Autodesk Fusion 360 part; units mm, degrees
(part 19 of 28)
  line L2184 (121.5447, 55.0726) -> (121.7003, 54.9596)
  line L2185 (121.7003, 54.9596) -> (121.8362, 54.8237)
  line L2186 (121.8362, 54.8237) -> (121.9492, 54.6682)
  line L2187 (121.9492, 54.6682) -> (122.0364, 54.4969)
  line L2188 (122.0364, 54.4969) -> (122.0958, 54.3141)
  line L2189 (122.0958, 54.3141) -> (122.1259, 54.1242)
  line L2190 (122.1259, 54.1242) -> (122.1297, 54.0281)
  line L2191 (122.1297, 54.0281) -> (122.1297, 53.4781)
  line L2192 (122.1297, 53.4781) -> (122.1259, 53.382)
  line L2193 (122.1259, 53.382) -> (122.0958, 53.1921)
  line L2194 (122.0958, 53.1921) -> (122.0364, 53.0093)
  line L2195 (122.0364, 53.0093) -> (121.9492, 52.8381)
  line L2196 (121.9492, 52.8381) -> (121.8362, 52.6825)
  line L2197 (121.8362, 52.6825) -> (121.7003, 52.5466)
  line L2198 (121.7003, 52.5466) -> (121.5447, 52.4336)
  line L2199 (121.5447, 52.4336) -> (121.3735, 52.3464)
  line L2200 (121.3735, 52.3464) -> (121.1907, 52.287)
  line L2201 (121.1907, 52.287) -> (121.0008, 52.2569)
  line L2202 (121.0008, 52.2569) -> (120.8086, 52.2569)
  line L2203 (120.8086, 52.2569) -> (120.6187, 52.287)
  line L2204 (120.6187, 52.287) -> (120.4359, 52.3464)
  line L2205 (120.4359, 52.3464) -> (120.2646, 52.4336)
  line L2206 (120.2646, 52.4336) -> (120.1091, 52.5466)
  line L2207 (120.1091, 52.5466) -> (119.9732, 52.6825)
  line L2208 (119.9732, 52.6825) -> (119.8602, 52.8381)
  line L2209 (119.8602, 52.8381) -> (119.7729, 53.0093)
  line L2210 (119.7729, 53.0093) -> (119.7135, 53.1921)
  line L2211 (119.7135, 53.1921) -> (119.6835, 53.382)
  line L2212 (119.6835, 53.382) -> (119.6797, 53.4781)
  line L2213 (119.6797, 53.4781) -> (119.6797, 54.0281)
  line L2214 (119.6797, 54.0281) -> (119.6835, 54.1242)
  line L2215 (119.6835, 54.1242) -> (119.7135, 54.3141)
  line L2216 (119.7135, 54.3141) -> (119.7729, 54.4969)
  line L2217 (119.7729, 54.4969) -> (119.8602, 54.6682)
  line L2218 (119.8602, 54.6682) -> (119.9732, 54.8237)
  line L2219 (119.9732, 54.8237) -> (120.1091, 54.9596)
  line L2220 (120.1091, 54.9596) -> (120.2646, 55.0726)
  line L2221 (120.2646, 55.0726) -> (120.4359, 55.1599)
  line L2222 (120.4359, 55.1599) -> (120.6187, 55.2193)
  line L2223 (120.6187, 55.2193) -> (120.8086, 55.2493)
  line L2224 (120.8086, 55.2493) -> (121.0008, 55.2493)
  line L2225 (121.0008, 55.2493) -> (121.1907, 55.2193)
  line L2226 (33.0099, 62.5572) -> (33.1964, 62.4966)
  line L2227 (33.1964, 62.4966) -> (33.3712, 62.4075)
  line L2228 (33.3712, 62.4075) -> (33.5299, 62.2922)
  line L2229 (33.5299, 62.2922) -> (33.6686, 62.1536)
  line L2230 (33.6686, 62.1536) -> (33.7838, 61.9949)
  line L2231 (33.7838, 61.9949) -> (33.8729, 61.8201)
  line L2232 (33.8729, 61.8201) -> (33.9335, 61.6335)
  line L2233 (33.9335, 61.6335) -> (33.9642, 61.4398)
  line L2234 (33.9642, 61.4398) -> (33.968, 61.3417)
  line L2235 (33.968, 61.3417) -> (33.968, 60.8417)
  line L2236 (33.968, 60.8417) -> (33.9642, 60.7437)
  line L2237 (33.9642, 60.7437) -> (33.9335, 60.5499)
  line L2238 (33.9335, 60.5499) -> (33.8729, 60.3634)
  line L2239 (33.8729, 60.3634) -> (33.7838, 60.1886)
  line L2240 (33.7838, 60.1886) -> (33.6686, 60.0299)
  line L2241 (33.6686, 60.0299) -> (33.5299, 59.8912)
  line L2242 (33.5299, 59.8912) -> (33.3712, 59.7759)
  line L2243 (33.3712, 59.7759) -> (33.1964, 59.6869)
  line L2244 (33.1964, 59.6869) -> (33.0098, 59.6263)
  line L2245 (33.0098, 59.6263) -> (32.8161, 59.5956)
  line L2246 (32.8161, 59.5956) -> (32.62, 59.5956)
  line L2247 (32.62, 59.5956) -> (32.4262, 59.6263)
  line L2248 (32.4262, 59.6263) -> (32.2397, 59.6869)
  line L2249 (32.2397, 59.6869) -> (32.0649, 59.7759)
  line L2250 (32.0649, 59.7759) -> (31.9062, 59.8912)
  line L2251 (31.9062, 59.8912) -> (31.7675, 60.0299)
  line L2252 (31.7675, 60.0299) -> (31.6522, 60.1886)
  line L2253 (31.6522, 60.1886) -> (31.5632, 60.3634)
  line L2254 (31.5632, 60.3634) -> (31.5026, 60.5499)
  line L2255 (31.5026, 60.5499) -> (31.4719, 60.7437)
  line L2256 (31.4719, 60.7437) -> (31.468, 60.8417)
  line L2257 (31.468, 60.8417) -> (31.468, 61.3417)
  line L2258 (31.468, 61.3417) -> (31.4719, 61.4398)
  line L2259 (31.4719, 61.4398) -> (31.5026, 61.6335)
  line L2260 (31.5026, 61.6335) -> (31.5632, 61.8201)
  line L2261 (31.5632, 61.8201) -> (31.6522, 61.9949)
  line L2262 (31.6522, 61.9949) -> (31.7675, 62.1536)
  line L2263 (31.7675, 62.1536) -> (31.9062, 62.2922)
  line L2264 (31.9062, 62.2922) -> (32.0649, 62.4075)
  line L2265 (32.0649, 62.4075) -> (32.2397, 62.4966)
  line L2266 (32.2397, 62.4966) -> (32.4262, 62.5572)
  line L2267 (32.4262, 62.5572) -> (32.62, 62.5879)
  line L2268 (32.62, 62.5879) -> (32.8161, 62.5879)
  line L2269 (32.8161, 62.5879) -> (33.0098, 62.5572)
  line L2270 (67.9348, 62.5572) -> (68.1214, 62.4966)
  line L2271 (68.1214, 62.4966) -> (68.2962, 62.4075)
  line L2272 (68.2962, 62.4075) -> (68.4549, 62.2922)
  line L2273 (68.4549, 62.2922) -> (68.5935, 62.1536)
  line L2274 (68.5935, 62.1536) -> (68.7088, 61.9949)
  line L2275 (68.7088, 61.9949) -> (68.7979, 61.8201)
  line L2276 (68.7979, 61.8201) -> (68.8585, 61.6335)
  line L2277 (68.8585, 61.6335) -> (68.8892, 61.4398)
  line L2278 (68.8892, 61.4398) -> (68.893, 61.3417)
  line L2279 (68.893, 61.3417) -> (68.893, 60.8417)
  line L2280 (68.893, 60.8417) -> (68.8892, 60.7437)
  line L2281 (68.8892, 60.7437) -> (68.8585, 60.5499)
  line L2282 (68.8585, 60.5499) -> (68.7979, 60.3634)
  line L2283 (68.7979, 60.3634) -> (68.7088, 60.1886)
  line L2284 (68.7088, 60.1886) -> (68.5935, 60.0299)
  line L2285 (68.5935, 60.0299) -> (68.4549, 59.8912)
  line L2286 (68.4549, 59.8912) -> (68.2962, 59.7759)
  line L2287 (68.2962, 59.7759) -> (68.1214, 59.6869)
  line L2288 (68.1214, 59.6869) -> (67.9348, 59.6263)
  line L2289 (67.9348, 59.6263) -> (67.7411, 59.5956)
  line L2290 (67.7411, 59.5956) -> (67.545, 59.5956)
  line L2291 (67.545, 59.5956) -> (67.3512, 59.6263)
  line L2292 (67.3512, 59.6263) -> (67.1647, 59.6869)
  line L2293 (67.1647, 59.6869) -> (66.9899, 59.7759)
  line L2294 (66.9899, 59.7759) -> (66.8312, 59.8912)
  line L2295 (66.8312, 59.8912) -> (66.6925, 60.0299)
  line L2296 (66.6925, 60.0299) -> (66.5772, 60.1886)
  line L2297 (66.5772, 60.1886) -> (66.4882, 60.3634)
  line L2298 (66.4882, 60.3634) -> (66.4276, 60.5499)
  line L2299 (66.4276, 60.5499) -> (66.3969, 60.7437)
  line L2300 (66.3969, 60.7437) -> (66.393, 60.8417)
  line L2301 (66.393, 60.8417) -> (66.393, 61.3417)
  line L2302 (66.393, 61.3417) -> (66.3969, 61.4398)
  line L2303 (66.3969, 61.4398) -> (66.4276, 61.6335)
  line L2304 (66.4276, 61.6335) -> (66.4882, 61.8201)
  line L2305 (66.4882, 61.8201) -> (66.5772, 61.9949)
  line L2306 (66.5772, 61.9949) -> (66.6925, 62.1536)
  line L2307 (66.6925, 62.1536) -> (66.8312, 62.2922)
  line L2308 (66.8312, 62.2922) -> (66.9899, 62.4075)
  line L2309 (66.9899, 62.4075) -> (67.1647, 62.4966)
  line L2310 (67.1647, 62.4966) -> (67.3512, 62.5572)
  line L2311 (67.3512, 62.5572) -> (67.545, 62.5879)
  line L2312 (67.545, 62.5879) -> (67.7411, 62.5879)
  line L2313 (67.7411, 62.5879) -> (67.9348, 62.5572)
  line L2314 (102.8598, 62.5572) -> (103.0464, 62.4966)
  line L2315 (103.0464, 62.4966) -> (103.2212, 62.4075)
  line L2316 (103.2212, 62.4075) -> (103.3799, 62.2922)
  line L2317 (103.3799, 62.2922) -> (103.5186, 62.1536)
  line L2318 (103.5186, 62.1536) -> (103.6338, 61.9949)
  line L2319 (103.6338, 61.9949) -> (103.7229, 61.8201)
  line L2320 (103.7229, 61.8201) -> (103.7835, 61.6335)
  line L2321 (103.7835, 61.6335) -> (103.8142, 61.4398)
  line L2322 (103.8142, 61.4398) -> (103.818, 61.3417)
  line L2323 (103.818, 61.3417) -> (103.818, 60.8417)
  line L2324 (103.818, 60.8417) -> (103.8142, 60.7437)
  line L2325 (103.8142, 60.7437) -> (103.7835, 60.5499)
  line L2326 (103.7835, 60.5499) -> (103.7229, 60.3634)
  line L2327 (103.7229, 60.3634) -> (103.6338, 60.1886)
  line L2328 (103.6338, 60.1886) -> (103.5186, 60.0299)
  line L2329 (103.5186, 60.0299) -> (103.3799, 59.8912)
  line L2330 (103.3799, 59.8912) -> (103.2212, 59.7759)
  line L2331 (103.2212, 59.7759) -> (103.0464, 59.6869)
  line L2332 (103.0464, 59.6869) -> (102.8598, 59.6263)
  line L2333 (102.8598, 59.6263) -> (102.6661, 59.5956)
  line L2334 (102.6661, 59.5956) -> (102.47, 59.5956)
  line L2335 (102.47, 59.5956) -> (102.2762, 59.6263)
  line L2336 (102.2762, 59.6263) -> (102.0897, 59.6869)
  line L2337 (102.0897, 59.6869) -> (101.9149, 59.7759)
  line L2338 (101.9149, 59.7759) -> (101.7562, 59.8912)
  line L2339 (101.7562, 59.8912) -> (101.6175, 60.0299)
  line L2340 (101.6175, 60.0299) -> (101.5022, 60.1886)
  line L2341 (101.5022, 60.1886) -> (101.4132, 60.3634)
  line L2342 (101.4132, 60.3634) -> (101.3526, 60.5499)
  line L2343 (101.3526, 60.5499) -> (101.3219, 60.7437)
  line L2344 (101.3219, 60.7437) -> (101.318, 60.8417)
  line L2345 (101.318, 60.8417) -> (101.318, 61.3417)
  line L2346 (101.318, 61.3417) -> (101.3219, 61.4398)
  line L2347 (101.3219, 61.4398) -> (101.3526, 61.6335)
  line L2348 (101.3526, 61.6335) -> (101.4132, 61.8201)
  line L2349 (101.4132, 61.8201) -> (101.5022, 61.9949)
  line L2350 (101.5022, 61.9949) -> (101.6175, 62.1536)
  line L2351 (101.6175, 62.1536) -> (101.7562, 62.2922)
  line L2352 (101.7562, 62.2922) -> (101.9149, 62.4075)
  line L2353 (101.9149, 62.4075) -> (102.0897, 62.4966)
  line L2354 (102.0897, 62.4966) -> (102.2762, 62.5572)
  line L2355 (102.2762, 62.5572) -> (102.47, 62.5879)
  line L2356 (102.47, 62.5879) -> (102.6661, 62.5879)
  line L2357 (102.6661, 62.5879) -> (102.8598, 62.5572)
  line L2358 (137.7849, 62.5572) -> (137.9714, 62.4966)
  line L2359 (137.9714, 62.4966) -> (138.1462, 62.4075)
  line L2360 (138.1462, 62.4075) -> (138.3049, 62.2922)
  line L2361 (138.3049, 62.2922) -> (138.4436, 62.1536)
  line L2362 (138.4436, 62.1536) -> (138.5588, 61.9949)
  line L2363 (138.5588, 61.9949) -> (138.6479, 61.8201)
  line L2364 (138.6479, 61.8201) -> (138.7085, 61.6335)
  line L2365 (138.7085, 61.6335) -> (138.7392, 61.4398)
  line L2366 (138.7392, 61.4398) -> (138.743, 61.3417)
  line L2367 (138.743, 61.3417) -> (138.743, 60.8417)
  line L2368 (138.743, 60.8417) -> (138.7392, 60.7437)
  line L2369 (138.7392, 60.7437) -> (138.7085, 60.5499)
  line L2370 (138.7085, 60.5499) -> (138.6479, 60.3634)
  line L2371 (138.6479, 60.3634) -> (138.5588, 60.1886)
  line L2372 (138.5588, 60.1886) -> (138.4436, 60.0299)
  line L2373 (138.4436, 60.0299) -> (138.3049, 59.8912)
  line L2374 (138.3049, 59.8912) -> (138.1462, 59.7759)
  line L2375 (138.1462, 59.7759) -> (137.9714, 59.6869)
  line L2376 (137.9714, 59.6869) -> (137.7849, 59.6263)
  line L2377 (137.7849, 59.6263) -> (137.5911, 59.5956)
  line L2378 (137.5911, 59.5956) -> (137.395, 59.5956)
  line L2379 (137.395, 59.5956) -> (137.2012, 59.6263)
  line L2380 (137.2012, 59.6263) -> (137.0147, 59.6869)
  line L2381 (137.0147, 59.6869) -> (136.8399, 59.7759)
  line L2382 (136.8399, 59.7759) -> (136.6812, 59.8912)
  line L2383 (136.6812, 59.8912) -> (136.5425, 60.0299)
  line L2384 (136.5425, 60.0299) -> (136.4272, 60.1886)
  line L2385 (136.4272, 60.1886) -> (136.3382, 60.3634)
  line L2386 (136.3382, 60.3634) -> (136.2776, 60.5499)
  line L2387 (136.2776, 60.5499) -> (136.2469, 60.7437)
  line L2388 (136.2469, 60.7437) -> (136.243, 60.8417)
  line L2389 (136.243, 60.8417) -> (136.243, 61.3417)
  line L2390 (136.243, 61.3417) -> (136.2469, 61.4398)
  line L2391 (136.2469, 61.4398) -> (136.2776, 61.6335)
  line L2392 (136.2776, 61.6335) -> (136.3382, 61.8201)
  line L2393 (136.3382, 61.8201) -> (136.4272, 61.9949)
  line L2394 (136.4272, 61.9949) -> (136.5425, 62.1536)
  line L2395 (136.5425, 62.1536) -> (136.6812, 62.2922)
  line L2396 (136.6812, 62.2922) -> (136.8399, 62.4075)
  line L2397 (136.8399, 62.4075) -> (137.0147, 62.4966)
  line L2398 (137.0147, 62.4966) -> (137.2012, 62.5572)
  line L2399 (137.2012, 62.5572) -> (137.395, 62.5879)
  line L2400 (137.395, 62.5879) -> (137.5911, 62.5879)
  line L2401 (137.5911, 62.5879) -> (137.7849, 62.5572)
  line L2402 (16.536, 65.4179) -> (16.7297, 65.3872)
  line L2403 (16.7297, 65.3872) -> (16.9162, 65.3266)
  line L2404 (16.9162, 65.3266) -> (17.091, 65.2376)
  line L2405 (17.091, 65.2376) -> (17.2497, 65.1223)
  line L2406 (17.2497, 65.1223) -> (17.3884, 64.9836)
  line L2407 (17.3884, 64.9836) -> (17.5037, 64.8249)
  line L2408 (17.5037, 64.8249) -> (17.5927, 64.6501)
  line L2409 (17.5927, 64.6501) -> (17.6534, 64.4636)
  line L2410 (17.6534, 64.4636) -> (17.684, 64.2698)
  line L2411 (17.684, 64.2698) -> (17.684, 64.0737)
  line L2412 (17.684, 64.0737) -> (17.6534, 63.88)
  line L2413 (17.6534, 63.88) -> (17.5927, 63.6934)
  line L2414 (17.5927, 63.6934) -> (17.5037, 63.5186)
  line L2415 (17.5037, 63.5186) -> (17.3884, 63.36)
  line L2416 (17.3884, 63.36) -> (17.2497, 63.2213)
  line L2417 (17.2497, 63.2213) -> (17.091, 63.106)
  line L2418 (17.091, 63.106) -> (16.9162, 63.0169)
  line L2419 (16.9162, 63.0169) -> (16.7297, 62.9563)
  line L2420 (16.7297, 62.9563) -> (16.536, 62.9256)
  line L2421 (16.536, 62.9256) -> (16.4379, 62.9218)
  line L2422 (16.4379, 62.9218) -> (15.9379, 62.9218)
  line L2423 (15.9379, 62.9218) -> (15.8398, 62.9256)
  line L2424 (15.8398, 62.9256) -> (15.6461, 62.9563)
  line L2425 (15.6461, 62.9563) -> (15.4595, 63.0169)
  line L2426 (15.4595, 63.0169) -> (15.2848, 63.106)
  line L2427 (15.2848, 63.106) -> (15.1261, 63.2213)
  line L2428 (15.1261, 63.2213) -> (14.9874, 63.36)
  line L2429 (14.9874, 63.36) -> (14.8721, 63.5186)
  line L2430 (14.8721, 63.5186) -> (14.783, 63.6934)
  line L2431 (14.783, 63.6934) -> (14.7224, 63.88)
  line L2432 (14.7224, 63.88) -> (14.6917, 64.0737)
  line L2433 (14.6917, 64.0737) -> (14.6917, 64.2698)
  line L2434 (14.6917, 64.2698) -> (14.7224, 64.4636)
  line L2435 (14.7224, 64.4636) -> (14.783, 64.6501)
  line L2436 (14.783, 64.6501) -> (14.8721, 64.8249)
  line L2437 (14.8721, 64.8249) -> (14.9874, 64.9836)
  line L2438 (14.9874, 64.9836) -> (15.1261, 65.1223)
  line L2439 (15.1261, 65.1223) -> (15.2848, 65.2376)
  line L2440 (15.2848, 65.2376) -> (15.4595, 65.3266)
  line L2441 (15.4595, 65.3266) -> (15.6461, 65.3872)
  line L2442 (15.6461, 65.3872) -> (15.8398, 65.4179)
  line L2443 (15.8398, 65.4179) -> (15.9379, 65.4218)
  line L2444 (15.9379, 65.4218) -> (16.4379, 65.4218)
  line L2445 (16.4379, 65.4218) -> (16.536, 65.4179)
  line L2446 (24.156, 65.4179) -> (24.3497, 65.3872)
  line L2447 (24.3497, 65.3872) -> (24.5362, 65.3266)
  line L2448 (24.5362, 65.3266) -> (24.711, 65.2376)
  line L2449 (24.711, 65.2376) -> (24.8697, 65.1223)
  line L2450 (24.8697, 65.1223) -> (25.0084, 64.9836)
  line L2451 (25.0084, 64.9836) -> (25.1237, 64.8249)
  line L2452 (25.1237, 64.8249) -> (25.2127, 64.6501)
  line L2453 (25.2127, 64.6501) -> (25.2734, 64.4636)
  line L2454 (25.2734, 64.4636) -> (25.304, 64.2698)
  line L2455 (25.304, 64.2698) -> (25.304, 64.0737)
  line L2456 (25.304, 64.0737) -> (25.2734, 63.88)
  line L2457 (25.2734, 63.88) -> (25.2127, 63.6934)
  line L2458 (25.2127, 63.6934) -> (25.1237, 63.5186)
  line L2459 (25.1237, 63.5186) -> (25.0084, 63.36)
  line L2460 (25.0084, 63.36) -> (24.8697, 63.2213)
  line L2461 (24.8697, 63.2213) -> (24.711, 63.106)
  line L2462 (24.711, 63.106) -> (24.5362, 63.0169)
  line L2463 (24.5362, 63.0169) -> (24.3497, 62.9563)
  line L2464 (24.3497, 62.9563) -> (24.156, 62.9256)
  line L2465 (24.156, 62.9256) -> (24.0579, 62.9218)
  line L2466 (24.0579, 62.9218) -> (23.5579, 62.9218)
  line L2467 (23.5579, 62.9218) -> (23.4598, 62.9256)
  line L2468 (23.4598, 62.9256) -> (23.2661, 62.9563)
  line L2469 (23.2661, 62.9563) -> (23.0795, 63.0169)
  line L2470 (23.0795, 63.0169) -> (22.9048, 63.106)
  line L2471 (22.9048, 63.106) -> (22.7461, 63.2213)
  line L2472 (22.7461, 63.2213) -> (22.6074, 63.36)
  line L2473 (22.6074, 63.36) -> (22.4921, 63.5186)
  line L2474 (22.4921, 63.5186) -> (22.403, 63.6934)
  line L2475 (22.403, 63.6934) -> (22.3424, 63.88)
  line L2476 (22.3424, 63.88) -> (22.3117, 64.0737)
  line L2477 (22.3117, 64.0737) -> (22.3117, 64.2698)
  line L2478 (22.3117, 64.2698) -> (22.3424, 64.4636)
  line L2479 (22.3424, 64.4636) -> (22.403, 64.6501)
  line L2480 (22.403, 64.6501) -> (22.4921, 64.8249)
  line L2481 (22.4921, 64.8249) -> (22.6074, 64.9836)
  line L2482 (22.6074, 64.9836) -> (22.7461, 65.1223)
  line L2483 (22.7461, 65.1223) -> (22.9048, 65.2376)
  line L2484 (22.9048, 65.2376) -> (23.0795, 65.3266)
  line L2485 (23.0795, 65.3266) -> (23.2661, 65.3872)
  line L2486 (23.2661, 65.3872) -> (23.4598, 65.4179)
  line L2487 (23.4598, 65.4179) -> (23.5579, 65.4218)
  line L2488 (23.5579, 65.4218) -> (24.0579, 65.4218)
  line L2489 (24.0579, 65.4218) -> (24.156, 65.4179)
  line L2490 (51.461, 65.4179) -> (51.6547, 65.3872)
  line L2491 (51.6547, 65.3872) -> (51.8412, 65.3266)
  line L2492 (51.8412, 65.3266) -> (52.016, 65.2376)
  line L2493 (52.016, 65.2376) -> (52.1747, 65.1223)
  line L2494 (52.1747, 65.1223) -> (52.3134, 64.9836)
  line L2495 (52.3134, 64.9836) -> (52.4287, 64.8249)
  line L2496 (52.4287, 64.8249) -> (52.5177, 64.6501)
  line L2497 (52.5177, 64.6501) -> (52.5784, 64.4636)
  line L2498 (52.5784, 64.4636) -> (52.609, 64.2698)
  line L2499 (52.609, 64.2698) -> (52.609, 64.0737)
  line L2500 (52.609, 64.0737) -> (52.5783, 63.88)
  line L2501 (52.5783, 63.88) -> (52.5177, 63.6934)
  line L2502 (52.5177, 63.6934) -> (52.4287, 63.5186)
  line L2503 (52.4287, 63.5186) -> (52.3134, 63.36)
  line L2504 (52.3134, 63.36) -> (52.1747, 63.2213)
  line L2505 (52.1747, 63.2213) -> (52.016, 63.106)
  line L2506 (52.016, 63.106) -> (51.8412, 63.0169)
  line L2507 (51.8412, 63.0169) -> (51.6547, 62.9563)
  line L2508 (51.6547, 62.9563) -> (51.461, 62.9256)
  line L2509 (51.461, 62.9256) -> (51.3629, 62.9218)
  line L2510 (51.3629, 62.9218) -> (50.8629, 62.9218)
  line L2511 (50.8629, 62.9218) -> (50.7648, 62.9256)
  line L2512 (50.7648, 62.9256) -> (50.5711, 62.9563)
  line L2513 (50.5711, 62.9563) -> (50.3845, 63.0169)
  line L2514 (50.3845, 63.0169) -> (50.2098, 63.106)
  line L2515 (50.2098, 63.106) -> (50.0511, 63.2213)
  line L2516 (50.0511, 63.2213) -> (49.9124, 63.36)
  line L2517 (49.9124, 63.36) -> (49.7971, 63.5186)
  line L2518 (49.7971, 63.5186) -> (49.708, 63.6934)
  line L2519 (49.708, 63.6934) -> (49.6474, 63.88)
  line L2520 (49.6474, 63.88) -> (49.6167, 64.0737)
  line L2521 (49.6167, 64.0737) -> (49.6167, 64.2698)
  line L2522 (49.6167, 64.2698) -> (49.6474, 64.4636)
  line L2523 (49.6474, 64.4636) -> (49.708, 64.6501)
  line L2524 (49.708, 64.6501) -> (49.7971, 64.8249)
  line L2525 (49.7971, 64.8249) -> (49.9124, 64.9836)
  line L2526 (49.9124, 64.9836) -> (50.0511, 65.1223)
  line L2527 (50.0511, 65.1223) -> (50.2098, 65.2376)
  line L2528 (50.2098, 65.2376) -> (50.3845, 65.3266)
  line L2529 (50.3845, 65.3266) -> (50.5711, 65.3872)
  line L2530 (50.5711, 65.3872) -> (50.7648, 65.4179)
  line L2531 (50.7648, 65.4179) -> (50.8629, 65.4218)
  line L2532 (50.8629, 65.4218) -> (51.3629, 65.4218)
  line L2533 (51.3629, 65.4218) -> (51.461, 65.4179)
  line L2534 (59.081, 65.4179) -> (59.2747, 65.3872)
  line L2535 (59.2747, 65.3872) -> (59.4612, 65.3266)
  line L2536 (59.4612, 65.3266) -> (59.636, 65.2376)
  line L2537 (59.636, 65.2376) -> (59.7947, 65.1223)
  line L2538 (59.7947, 65.1223) -> (59.9334, 64.9836)
  line L2539 (59.9334, 64.9836) -> (60.0487, 64.8249)
  line L2540 (60.0487, 64.8249) -> (60.1377, 64.6501)
  line L2541 (60.1377, 64.6501) -> (60.1984, 64.4636)
  line L2542 (60.1984, 64.4636) -> (60.229, 64.2698)
  line L2543 (60.229, 64.2698) -> (60.229, 64.0737)
  line L2544 (60.229, 64.0737) -> (60.1983, 63.88)
  line L2545 (60.1983, 63.88) -> (60.1377, 63.6934)
  line L2546 (60.1377, 63.6934) -> (60.0487, 63.5186)
  line L2547 (60.0487, 63.5186) -> (59.9334, 63.36)
  line L2548 (59.9334, 63.36) -> (59.7947, 63.2213)
  line L2549 (59.7947, 63.2213) -> (59.636, 63.106)
  line L2550 (59.636, 63.106) -> (59.4612, 63.0169)
  line L2551 (59.4612, 63.0169) -> (59.2747, 62.9563)
  line L2552 (59.2747, 62.9563) -> (59.081, 62.9256)
  line L2553 (59.081, 62.9256) -> (58.9829, 62.9218)
  line L2554 (58.9829, 62.9218) -> (58.4829, 62.9218)
  line L2555 (58.4829, 62.9218) -> (58.3848, 62.9256)
  line L2556 (58.3848, 62.9256) -> (58.1911, 62.9563)
  line L2557 (58.1911, 62.9563) -> (58.0045, 63.0169)
  line L2558 (58.0045, 63.0169) -> (57.8298, 63.106)
  line L2559 (57.8298, 63.106) -> (57.6711, 63.2213)
  line L2560 (57.6711, 63.2213) -> (57.5324, 63.36)
  line L2561 (57.5324, 63.36) -> (57.4171, 63.5186)
  line L2562 (57.4171, 63.5186) -> (57.328, 63.6934)
  line L2563 (57.328, 63.6934) -> (57.2674, 63.88)
  line L2564 (57.2674, 63.88) -> (57.2367, 64.0737)
  line L2565 (57.2367, 64.0737) -> (57.2367, 64.2698)
  line L2566 (57.2367, 64.2698) -> (57.2674, 64.4636)
  line L2567 (57.2674, 64.4636) -> (57.328, 64.6501)
  line L2568 (57.328, 64.6501) -> (57.4171, 64.8249)
  line L2569 (57.4171, 64.8249) -> (57.5324, 64.9836)
  line L2570 (57.5324, 64.9836) -> (57.6711, 65.1223)
  line L2571 (57.6711, 65.1223) -> (57.8298, 65.2376)
  line L2572 (57.8298, 65.2376) -> (58.0045, 65.3266)
  line L2573 (58.0045, 65.3266) -> (58.1911, 65.3872)
  line L2574 (58.1911, 65.3872) -> (58.3848, 65.4179)
  line L2575 (58.3848, 65.4179) -> (58.4829, 65.4218)
  line L2576 (58.4829, 65.4218) -> (58.9829, 65.4218)
  line L2577 (58.9829, 65.4218) -> (59.081, 65.4179)
  line L2578 (86.386, 65.4179) -> (86.5797, 65.3872)
  line L2579 (86.5797, 65.3872) -> (86.7662, 65.3266)
  line L2580 (86.7662, 65.3266) -> (86.941, 65.2376)
  line L2581 (86.941, 65.2376) -> (87.0997, 65.1223)
  line L2582 (87.0997, 65.1223) -> (87.2384, 64.9836)
  line L2583 (87.2384, 64.9836) -> (87.3537, 64.8249)
  line L2584 (87.3537, 64.8249) -> (87.4427, 64.6501)
  line L2585 (87.4427, 64.6501) -> (87.5034, 64.4636)
  line L2586 (87.5034, 64.4636) -> (87.534, 64.2698)
  line L2587 (87.534, 64.2698) -> (87.534, 64.0737)
  line L2588 (87.534, 64.0737) -> (87.5034, 63.88)
  line L2589 (87.5033, 63.88) -> (87.4427, 63.6934)
  line L2590 (87.4427, 63.6934) -> (87.3537, 63.5186)
  line L2591 (87.3537, 63.5186) -> (87.2384, 63.36)
  line L2592 (87.2384, 63.36) -> (87.0997, 63.2213)
  line L2593 (87.0997, 63.2213) -> (86.941, 63.106)
  line L2594 (86.941, 63.106) -> (86.7662, 63.0169)
  line L2595 (86.7662, 63.0169) -> (86.5797, 62.9563)
  line L2596 (86.5797, 62.9563) -> (86.386, 62.9256)
  line L2597 (86.386, 62.9256) -> (86.2879, 62.9218)
  line L2598 (86.2879, 62.9218) -> (85.7879, 62.9218)
  line L2599 (85.7879, 62.9218) -> (85.6898, 62.9256)
  line L2600 (85.6898, 62.9256) -> (85.4961, 62.9563)
  line L2601 (85.4961, 62.9563) -> (85.3095, 63.0169)
  line L2602 (85.3095, 63.0169) -> (85.1348, 63.106)
  line L2603 (85.1348, 63.106) -> (84.9761, 63.2213)
  line L2604 (84.9761, 63.2213) -> (84.8374, 63.36)
  line L2605 (84.8374, 63.36) -> (84.7221, 63.5186)
  line L2606 (84.7221, 63.5186) -> (84.633, 63.6934)
  line L2607 (84.633, 63.6934) -> (84.5724, 63.88)
  line L2608 (84.5724, 63.88) -> (84.5417, 64.0737)
  line L2609 (84.5417, 64.0737) -> (84.5417, 64.2698)
  line L2610 (84.5417, 64.2698) -> (84.5724, 64.4636)
  line L2611 (84.5724, 64.4636) -> (84.633, 64.6501)
  line L2612 (84.633, 64.6501) -> (84.7221, 64.8249)
  line L2613 (84.7221, 64.8249) -> (84.8374, 64.9836)
  line L2614 (84.8374, 64.9836) -> (84.9761, 65.1223)
  line L2615 (84.9761, 65.1223) -> (85.1348, 65.2376)
  line L2616 (85.1348, 65.2376) -> (85.3095, 65.3266)
  line L2617 (85.3095, 65.3266) -> (85.4961, 65.3872)
  line L2618 (85.4961, 65.3872) -> (85.6898, 65.4179)
  line L2619 (85.6898, 65.4179) -> (85.7879, 65.4218)
  line L2620 (85.7879, 65.4218) -> (86.2879, 65.4218)
  line L2621 (86.2879, 65.4218) -> (86.386, 65.4179)
  line L2622 (94.006, 65.4179) -> (94.1997, 65.3872)
  line L2623 (94.1997, 65.3872) -> (94.3862, 65.3266)
  line L2624 (94.3862, 65.3266) -> (94.561, 65.2376)
  line L2625 (94.561, 65.2376) -> (94.7197, 65.1223)
  line L2626 (94.7197, 65.1223) -> (94.8584, 64.9836)
  line L2627 (94.8584, 64.9836) -> (94.9737, 64.8249)
  line L2628 (94.9737, 64.8249) -> (95.0627, 64.6501)
  line L2629 (95.0627, 64.6501) -> (95.1233, 64.4636)
  line L2630 (95.1233, 64.4636) -> (95.154, 64.2698)
  line L2631 (95.154, 64.2698) -> (95.154, 64.0737)
  line L2632 (95.154, 64.0737) -> (95.1233, 63.88)
  line L2633 (95.1233, 63.88) -> (95.0627, 63.6934)
  line L2634 (95.0627, 63.6934) -> (94.9737, 63.5186)
  line L2635 (94.9737, 63.5186) -> (94.8584, 63.36)
  line L2636 (94.8584, 63.36) -> (94.7197, 63.2213)
  line L2637 (94.7197, 63.2213) -> (94.561, 63.106)
  line L2638 (94.561, 63.106) -> (94.3862, 63.0169)
  line L2639 (94.3862, 63.0169) -> (94.1997, 62.9563)
  line L2640 (94.1997, 62.9563) -> (94.006, 62.9256)
  line L2641 (94.006, 62.9256) -> (93.9079, 62.9218)
  line L2642 (93.9079, 62.9218) -> (93.4079, 62.9218)
  line L2643 (93.4079, 62.9218) -> (93.3098, 62.9256)
  line L2644 (93.3098, 62.9256) -> (93.1161, 62.9563)
  line L2645 (93.1161, 62.9563) -> (92.9295, 63.0169)
  line L2646 (92.9295, 63.0169) -> (92.7548, 63.106)
  line L2647 (92.7548, 63.106) -> (92.5961, 63.2213)
  line L2648 (92.5961, 63.2213) -> (92.4574, 63.36)
  line L2649 (92.4574, 63.36) -> (92.3421, 63.5186)
  line L2650 (92.3421, 63.5186) -> (92.253, 63.6934)
  line L2651 (92.253, 63.6934) -> (92.1924, 63.88)
  line L2652 (92.1924, 63.88) -> (92.1617, 64.0737)
  line L2653 (92.1617, 64.0737) -> (92.1617, 64.2698)
  line L2654 (92.1617, 64.2698) -> (92.1924, 64.4636)
  line L2655 (92.1924, 64.4636) -> (92.253, 64.6501)
  line L2656 (92.253, 64.6501) -> (92.3421, 64.8249)
  line L2657 (92.3421, 64.8249) -> (92.4574, 64.9836)
  line L2658 (92.4574, 64.9836) -> (92.5961, 65.1223)
  line L2659 (92.5961, 65.1223) -> (92.7548, 65.2376)
  line L2660 (92.7548, 65.2376) -> (92.9295, 65.3266)
  line L2661 (92.9295, 65.3266) -> (93.1161, 65.3872)
  line L2662 (93.1161, 65.3872) -> (93.3098, 65.4179)
  line L2663 (93.3098, 65.4179) -> (93.4079, 65.4218)
  line L2664 (93.4079, 65.4218) -> (93.9079, 65.4218)
  line L2665 (93.9079, 65.4218) -> (94.006, 65.4179)
  line L2666 (121.311, 65.4179) -> (121.5047, 65.3872)
  line L2667 (121.5047, 65.3872) -> (121.6912, 65.3266)
  line L2668 (121.6912, 65.3266) -> (121.866, 65.2376)
  line L2669 (121.866, 65.2376) -> (122.0247, 65.1223)
  line L2670 (122.0247, 65.1223) -> (122.1634, 64.9836)
  line L2671 (122.1634, 64.9836) -> (122.2787, 64.8249)
  line L2672 (122.2787, 64.8249) -> (122.3677, 64.6501)
  line L2673 (122.3677, 64.6501) -> (122.4283, 64.4636)
  line L2674 (122.4283, 64.4636) -> (122.459, 64.2698)
  line L2675 (122.459, 64.2698) -> (122.459, 64.0737)
  line L2676 (122.459, 64.0737) -> (122.4283, 63.88)
  line L2677 (122.4283, 63.88) -> (122.3677, 63.6934)
  line L2678 (122.3677, 63.6934) -> (122.2787, 63.5186)
  line L2679 (122.2787, 63.5186) -> (122.1634, 63.36)
  line L2680 (122.1634, 63.36) -> (122.0247, 63.2213)
  line L2681 (122.0247, 63.2213) -> (121.866, 63.106)
  line L2682 (121.866, 63.106) -> (121.6912, 63.0169)
  line L2683 (121.6912, 63.0169) -> (121.5047, 62.9563)
  line L2684 (121.5047, 62.9563) -> (121.311, 62.9256)
  line L2685 (121.311, 62.9256) -> (121.2129, 62.9218)
  line L2686 (121.2129, 62.9218) -> (120.7129, 62.9218)
  line L2687 (120.7129, 62.9218) -> (120.6148, 62.9256)
  line L2688 (120.6148, 62.9256) -> (120.4211, 62.9563)
  line L2689 (120.4211, 62.9563) -> (120.2345, 63.0169)
  line L2690 (120.2345, 63.0169) -> (120.0598, 63.106)
  line L2691 (120.0598, 63.106) -> (119.9011, 63.2213)
  line L2692 (119.9011, 63.2213) -> (119.7624, 63.36)
  line L2693 (119.7624, 63.36) -> (119.6471, 63.5186)
  line L2694 (119.6471, 63.5186) -> (119.558, 63.6934)
  line L2695 (119.558, 63.6934) -> (119.4974, 63.88)
  line L2696 (119.4974, 63.88) -> (119.4667, 64.0737)
  line L2697 (119.4667, 64.0737) -> (119.4667, 64.2698)
  line L2698 (119.4667, 64.2698) -> (119.4974, 64.4636)
  line L2699 (119.4974, 64.4636) -> (119.558, 64.6501)
  line L2700 (119.558, 64.6501) -> (119.6471, 64.8249)
  line L2701 (119.6471, 64.8249) -> (119.7624, 64.9836)
  line L2702 (119.7624, 64.9836) -> (119.9011, 65.1223)
  line L2703 (119.9011, 65.1223) -> (120.0598, 65.2376)
  line L2704 (120.0598, 65.2376) -> (120.2345, 65.3266)
  line L2705 (120.2345, 65.3266) -> (120.4211, 65.3872)
  line L2706 (120.4211, 65.3872) -> (120.6148, 65.4179)
  line L2707 (120.6148, 65.4179) -> (120.7129, 65.4218)
  line L2708 (120.7129, 65.4218) -> (121.2129, 65.4218)
  line L2709 (121.2129, 65.4218) -> (121.311, 65.4179)
  line L2710 (128.931, 65.4179) -> (129.1247, 65.3872)
  line L2711 (129.1247, 65.3872) -> (129.3112, 65.3266)
  line L2712 (129.3112, 65.3266) -> (129.486, 65.2376)
  line L2713 (129.486, 65.2376) -> (129.6447, 65.1223)
  line L2714 (129.6447, 65.1223) -> (129.7834, 64.9836)
  line L2715 (129.7834, 64.9836) -> (129.8987, 64.8249)
  line L2716 (129.8987, 64.8249) -> (129.9877, 64.6501)
  line L2717 (129.9877, 64.6501) -> (130.0483, 64.4636)
  line L2718 (130.0483, 64.4636) -> (130.079, 64.2698)
  line L2719 (130.079, 64.2698) -> (130.079, 64.0737)
  line L2720 (130.079, 64.0737) -> (130.0483, 63.88)
  line L2721 (130.0483, 63.88) -> (129.9877, 63.6934)
  line L2722 (129.9877, 63.6934) -> (129.8987, 63.5186)
  line L2723 (129.8987, 63.5186) -> (129.7834, 63.36)
  line L2724 (129.7834, 63.36) -> (129.6447, 63.2213)
  line L2725 (129.6447, 63.2213) -> (129.486, 63.106)
  line L2726 (129.486, 63.106) -> (129.3112, 63.0169)
  line L2727 (129.3112, 63.0169) -> (129.1247, 62.9563)
  line L2728 (129.1247, 62.9563) -> (128.931, 62.9256)
  line L2729 (128.931, 62.9256) -> (128.8329, 62.9218)
  line L2730 (128.8329, 62.9218) -> (128.3329, 62.9218)
  line L2731 (128.3329, 62.9218) -> (128.2348, 62.9256)
  line L2732 (128.2348, 62.9256) -> (128.0411, 62.9563)
  line L2733 (128.0411, 62.9563) -> (127.8545, 63.0169)
  line L2734 (127.8545, 63.0169) -> (127.6798, 63.106)
  line L2735 (127.6798, 63.106) -> (127.5211, 63.2213)
  line L2736 (127.5211, 63.2213) -> (127.3824, 63.36)
  line L2737 (127.3824, 63.36) -> (127.2671, 63.5186)
  line L2738 (127.2671, 63.5186) -> (127.178, 63.6934)
  line L2739 (127.178, 63.6934) -> (127.1174, 63.88)
  line L2740 (127.1174, 63.88) -> (127.0867, 64.0737)
  line L2741 (127.0867, 64.0737) -> (127.0867, 64.2698)
  line L2742 (127.0867, 64.2698) -> (127.1174, 64.4636)
  line L2743 (127.1174, 64.4636) -> (127.178, 64.6501)
  line L2744 (127.178, 64.6501) -> (127.2671, 64.8249)
  line L2745 (127.2671, 64.8249) -> (127.3824, 64.9836)
  line L2746 (127.3824, 64.9836) -> (127.5211, 65.1223)
  line L2747 (127.5211, 65.1223) -> (127.6798, 65.2376)
  line L2748 (127.6798, 65.2376) -> (127.8545, 65.3266)
  line L2749 (127.8545, 65.3266) -> (128.0411, 65.3872)
  line L2750 (128.0411, 65.3872) -> (128.2348, 65.4179)
  line L2751 (128.2348, 65.4179) -> (128.3329, 65.4218)
  line L2752 (128.3329, 65.4218) -> (128.8329, 65.4218)
  line L2753 (128.8329, 65.4218) -> (128.931, 65.4179)
  line L2754 (33.0099, 70.1772) -> (33.1964, 70.1166)
  line L2755 (33.1964, 70.1166) -> (33.3712, 70.0275)
  line L2756 (33.3712, 70.0275) -> (33.5299, 69.9122)
  line L2757 (33.5299, 69.9122) -> (33.6686, 69.7736)
  line L2758 (33.6686, 69.7736) -> (33.7838, 69.6149)
  line L2759 (33.7838, 69.6149) -> (33.8729, 69.4401)
  line L2760 (33.8729, 69.4401) -> (33.9335, 69.2535)
  line L2761 (33.9335, 69.2535) -> (33.9642, 69.0598)
  line L2762 (33.9642, 69.0598) -> (33.968, 68.9617)
  line L2763 (33.968, 68.9617) -> (33.968, 68.4617)
  line L2764 (33.968, 68.4617) -> (33.9642, 68.3637)
  line L2765 (33.9642, 68.3637) -> (33.9335, 68.1699)
  line L2766 (33.9335, 68.1699) -> (33.8729, 67.9834)
  line L2767 (33.8729, 67.9834) -> (33.7838, 67.8086)
  line L2768 (33.7838, 67.8086) -> (33.6686, 67.6499)
  line L2769 (33.6686, 67.6499) -> (33.5299, 67.5112)
  line L2770 (33.5299, 67.5112) -> (33.3712, 67.3959)
  line L2771 (33.3712, 67.3959) -> (33.1964, 67.3069)
  line L2772 (33.1964, 67.3069) -> (33.0098, 67.2463)
  line L2773 (33.0098, 67.2463) -> (32.8161, 67.2156)
  line L2774 (32.8161, 67.2156) -> (32.62, 67.2156)
  line L2775 (32.62, 67.2156) -> (32.4262, 67.2463)
  line L2776 (32.4262, 67.2463) -> (32.2397, 67.3069)
  line L2777 (32.2397, 67.3069) -> (32.0649, 67.3959)
  line L2778 (32.0649, 67.3959) -> (31.9062, 67.5112)
  line L2779 (31.9062, 67.5112) -> (31.7675, 67.6499)
  line L2780 (31.7675, 67.6499) -> (31.6522, 67.8086)
  line L2781 (31.6522, 67.8086) -> (31.5632, 67.9834)
  line L2782 (31.5632, 67.9834) -> (31.5026, 68.1699)
  line L2783 (31.5026, 68.1699) -> (31.4719, 68.3637)
  line L2784 (31.4719, 68.3637) -> (31.468, 68.4617)
  line L2785 (31.468, 68.4617) -> (31.468, 68.9617)
  line L2786 (31.468, 68.9617) -> (31.4719, 69.0598)
  line L2787 (31.4719, 69.0598) -> (31.5026, 69.2535)
  line L2788 (31.5026, 69.2535) -> (31.5632, 69.4401)
  line L2789 (31.5632, 69.4401) -> (31.6522, 69.6149)
  line L2790 (31.6522, 69.6149) -> (31.7675, 69.7736)
  line L2791 (31.7675, 69.7736) -> (31.9062, 69.9122)
  line L2792 (31.9062, 69.9122) -> (32.0649, 70.0275)
  line L2793 (32.0649, 70.0275) -> (32.2397, 70.1166)
  line L2794 (32.2397, 70.1166) -> (32.4262, 70.1772)
  line L2795 (32.4262, 70.1772) -> (32.62, 70.2079)
  line L2796 (32.62, 70.2079) -> (32.8161, 70.2079)
  line L2797 (32.8161, 70.2079) -> (33.0098, 70.1772)
  line L2798 (67.9348, 70.1772) -> (68.1214, 70.1166)
  line L2799 (68.1214, 70.1166) -> (68.2962, 70.0275)
  line L2800 (68.2962, 70.0275) -> (68.4549, 69.9122)
  line L2801 (68.4549, 69.9122) -> (68.5935, 69.7736)
  line L2802 (68.5935, 69.7736) -> (68.7088, 69.6149)
  line L2803 (68.7088, 69.6149) -> (68.7979, 69.4401)
  line L2804 (68.7979, 69.4401) -> (68.8585, 69.2535)
  line L2805 (68.8585, 69.2535) -> (68.8892, 69.0598)
  line L2806 (68.8892, 69.0598) -> (68.893, 68.9617)
  line L2807 (68.893, 68.9617) -> (68.893, 68.4617)
  line L2808 (68.893, 68.4617) -> (68.8892, 68.3637)
  line L2809 (68.8892, 68.3637) -> (68.8585, 68.1699)
  line L2810 (68.8585, 68.1699) -> (68.7979, 67.9834)
  line L2811 (68.7979, 67.9834) -> (68.7088, 67.8086)
  line L2812 (68.7088, 67.8086) -> (68.5935, 67.6499)
  line L2813 (68.5935, 67.6499) -> (68.4549, 67.5112)
  line L2814 (68.4549, 67.5112) -> (68.2962, 67.3959)
  line L2815 (68.2962, 67.3959) -> (68.1214, 67.3069)
  line L2816 (68.1214, 67.3069) -> (67.9348, 67.2463)
  line L2817 (67.9348, 67.2463) -> (67.7411, 67.2156)
  line L2818 (67.7411, 67.2156) -> (67.545, 67.2156)
  line L2819 (67.545, 67.2156) -> (67.3512, 67.2463)
  line L2820 (67.3512, 67.2463) -> (67.1647, 67.3069)
  line L2821 (67.1647, 67.3069) -> (66.9899, 67.3959)
  line L2822 (66.9899, 67.3959) -> (66.8312, 67.5112)
  line L2823 (66.8312, 67.5112) -> (66.6925, 67.6499)
  line L2824 (66.6925, 67.6499) -> (66.5772, 67.8086)
  line L2825 (66.5772, 67.8086) -> (66.4882, 67.9834)
  line L2826 (66.4882, 67.9834) -> (66.4276, 68.1699)
  line L2827 (66.4276, 68.1699) -> (66.3969, 68.3637)
  line L2828 (66.3969, 68.3637) -> (66.393, 68.4617)
  line L2829 (66.393, 68.4617) -> (66.393, 68.9617)
  line L2830 (66.393, 68.9617) -> (66.3969, 69.0598)
  line L2831 (66.3969, 69.0598) -> (66.4276, 69.2535)
  line L2832 (66.4276, 69.2535) -> (66.4882, 69.4401)
  line L2833 (66.4882, 69.4401) -> (66.5772, 69.6149)
  line L2834 (66.5772, 69.6149) -> (66.6925, 69.7736)
  line L2835 (66.6925, 69.7736) -> (66.8312, 69.9122)
  line L2836 (66.8312, 69.9122) -> (66.9899, 70.0275)
  line L2837 (66.9899, 70.0275) -> (67.1647, 70.1166)
  line L2838 (67.1647, 70.1166) -> (67.3512, 70.1772)
  line L2839 (67.3512, 70.1772) -> (67.545, 70.2079)
  line L2840 (67.545, 70.2079) -> (67.7411, 70.2079)
  line L2841 (67.7411, 70.2079) -> (67.9348, 70.1772)
  line L2842 (102.8598, 70.1772) -> (103.0464, 70.1166)
  line L2843 (103.0464, 70.1166) -> (103.2212, 70.0275)
  line L2844 (103.2212, 70.0275) -> (103.3799, 69.9122)
  line L2845 (103.3799, 69.9122) -> (103.5186, 69.7736)
  line L2846 (103.5186, 69.7736) -> (103.6338, 69.6149)
  line L2847 (103.6338, 69.6149) -> (103.7229, 69.4401)
  line L2848 (103.7229, 69.4401) -> (103.7835, 69.2535)
  line L2849 (103.7835, 69.2535) -> (103.8142, 69.0598)
  line L2850 (103.8142, 69.0598) -> (103.818, 68.9617)
  line L2851 (103.818, 68.9617) -> (103.818, 68.4617)
  line L2852 (103.818, 68.4617) -> (103.8142, 68.3637)
  line L2853 (103.8142, 68.3637) -> (103.7835, 68.1699)
  line L2854 (103.7835, 68.1699) -> (103.7229, 67.9834)
  line L2855 (103.7229, 67.9834) -> (103.6338, 67.8086)
  line L2856 (103.6338, 67.8086) -> (103.5186, 67.6499)
  line L2857 (103.5186, 67.6499) -> (103.3799, 67.5112)
  line L2858 (103.3799, 67.5112) -> (103.2212, 67.3959)
  line L2859 (103.2212, 67.3959) -> (103.0464, 67.3069)
  line L2860 (103.0464, 67.3069) -> (102.8598, 67.2463)
  line L2861 (102.8598, 67.2463) -> (102.6661, 67.2156)
  line L2862 (102.6661, 67.2156) -> (102.47, 67.2156)
  line L2863 (102.47, 67.2156) -> (102.2762, 67.2463)
  line L2864 (102.2762, 67.2463) -> (102.0897, 67.3069)
  line L2865 (102.0897, 67.3069) -> (101.9149, 67.3959)
  line L2866 (101.9149, 67.3959) -> (101.7562, 67.5112)
  line L2867 (101.7562, 67.5112) -> (101.6175, 67.6499)
  line L2868 (101.6175, 67.6499) -> (101.5022, 67.8086)
  line L2869 (101.5022, 67.8086) -> (101.4132, 67.9834)
  line L2870 (101.4132, 67.9834) -> (101.3526, 68.1699)
  line L2871 (101.3526, 68.1699) -> (101.3219, 68.3637)
  line L2872 (101.3219, 68.3637) -> (101.318, 68.4617)
  line L2873 (101.318, 68.4617) -> (101.318, 68.9617)
  line L2874 (101.318, 68.9617) -> (101.3219, 69.0598)
  line L2875 (101.3219, 69.0598) -> (101.3526, 69.2535)
  line L2876 (101.3526, 69.2535) -> (101.4132, 69.4401)
  line L2877 (101.4132, 69.4401) -> (101.5022, 69.6149)
  line L2878 (101.5022, 69.6149) -> (101.6175, 69.7736)
  line L2879 (101.6175, 69.7736) -> (101.7562, 69.9122)
  line L2880 (101.7562, 69.9122) -> (101.9149, 70.0275)
  line L2881 (101.9149, 70.0275) -> (102.0897, 70.1166)
  line L2882 (102.0897, 70.1166) -> (102.2762, 70.1772)
  line L2883 (102.2762, 70.1772) -> (102.47, 70.2079)
  line L2884 (102.47, 70.2079) -> (102.6661, 70.2079)
  line L2885 (102.6661, 70.2079) -> (102.8598, 70.1772)
  line L2886 (137.7849, 70.1772) -> (137.9714, 70.1166)
  line L2887 (137.9714, 70.1166) -> (138.1462, 70.0275)
  line L2888 (138.1462, 70.0275) -> (138.3049, 69.9122)
  line L2889 (138.3049, 69.9122) -> (138.4436, 69.7736)
  line L2890 (138.4436, 69.7736) -> (138.5588, 69.6149)
  line L2891 (138.5588, 69.6149) -> (138.6479, 69.4401)
  line L2892 (138.6479, 69.4401) -> (138.7085, 69.2535)
  line L2893 (138.7085, 69.2535) -> (138.7392, 69.0598)
  line L2894 (138.7392, 69.0598) -> (138.743, 68.9617)
  line L2895 (138.743, 68.9617) -> (138.743, 68.4617)
  line L2896 (138.743, 68.4617) -> (138.7392, 68.3637)
  line L2897 (138.7392, 68.3637) -> (138.7085, 68.1699)
  line L2898 (138.7085, 68.1699) -> (138.6479, 67.9834)
  line L2899 (138.6479, 67.9834) -> (138.5588, 67.8086)
  line L2900 (138.5588, 67.8086) -> (138.4436, 67.6499)
  line L2901 (138.4436, 67.6499) -> (138.3049, 67.5112)
  line L2902 (138.3049, 67.5112) -> (138.1462, 67.3959)
  line L2903 (138.1462, 67.3959) -> (137.9714, 67.3069)
  line L2904 (137.9714, 67.3069) -> (137.7849, 67.2463)
  line L2905 (137.7849, 67.2463) -> (137.5911, 67.2156)
  line L2906 (137.5911, 67.2156) -> (137.395, 67.2156)
  line L2907 (137.395, 67.2156) -> (137.2012, 67.2463)
  line L2908 (137.2012, 67.2463) -> (137.0147, 67.3069)
  line L2909 (137.0147, 67.3069) -> (136.8399, 67.3959)
  line L2910 (136.8399, 67.3959) -> (136.6812, 67.5112)
  line L2911 (136.6812, 67.5112) -> (136.5425, 67.6499)
  line L2912 (136.5425, 67.6499) -> (136.4272, 67.8086)
  line L2913 (136.4272, 67.8086) -> (136.3382, 67.9834)
  line L2914 (136.3382, 67.9834) -> (136.2776, 68.1699)
  line L2915 (136.2776, 68.1699) -> (136.2469, 68.3637)
  line L2916 (136.2469, 68.3637) -> (136.243, 68.4617)
  line L2917 (136.243, 68.4617) -> (136.243, 68.9617)
  line L2918 (136.243, 68.9617) -> (136.2469, 69.0598)
  line L2919 (136.2469, 69.0598) -> (136.2776, 69.2535)
  line L2920 (136.2776, 69.2535) -> (136.3382, 69.4401)
  line L2921 (136.3382, 69.4401) -> (136.4272, 69.6149)
  line L2922 (136.4272, 69.6149) -> (136.5425, 69.7736)
  line L2923 (136.5425, 69.7736) -> (136.6812, 69.9122)
  line L2924 (136.6812, 69.9122) -> (136.8399, 70.0275)
  line L2925 (136.8399, 70.0275) -> (137.0147, 70.1166)
  line L2926 (137.0147, 70.1166) -> (137.2012, 70.1772)
  line L2927 (137.2012, 70.1772) -> (137.395, 70.2079)
  line L2928 (137.395, 70.2079) -> (137.5911, 70.2079)
  line L2929 (137.5911, 70.2079) -> (137.7849, 70.1772)
  line L2930 (24.9416, 73.2403) -> (22.9416, 73.2403)
  line L2931 (22.9416, 73.2403) -> (22.9416, 76.4403)
  line L2932 (22.9416, 76.4403) -> (24.9416, 76.4403)
  line L2933 (24.9416, 76.4403) -> (24.9416, 73.2403)
  line L2934 (59.8666, 73.2403) -> (57.8666, 73.2403)
  line L2935 (57.8666, 73.2403) -> (57.8666, 76.4403)
  line L2936 (57.8666, 76.4403) -> (59.8666, 76.4403)
  line L2937 (59.8666, 76.4403) -> (59.8666, 73.2403)
  line L2938 (94.7916, 73.2403) -> (92.7916, 73.2403)
  line L2939 (92.7916, 73.2403) -> (92.7916, 76.4403)
  line L2940 (92.7916, 76.4403) -> (94.7916, 76.4403)
  line L2941 (94.7916, 76.4403) -> (94.7916, 73.2403)
  line L2942 (129.7166, 73.2403) -> (127.7166, 73.2403)
  line L2943 (127.7166, 73.2403) -> (127.7166, 76.4403)
  line L2944 (127.7166, 76.4403) -> (129.7166, 76.4403)
  line L2945 (129.7166, 76.4403) -> (129.7166, 73.2403)
  line L2946 (27.0019, 76.3972) -> (27.183, 76.3222)
  line L2947 (27.183, 76.3222) -> (27.346, 76.2133)
  line L2948 (27.346, 76.2133) -> (27.4846, 76.0747)
  line L2949 (27.4846, 76.0747) -> (27.5935, 75.9117)
  line L2950 (27.5935, 75.9117) -> (27.6685, 75.7306)
  line L2951 (27.6685, 75.7306) -> (27.7068, 75.5383)
  line L2952 (27.7068, 75.5383) -> (27.7116, 75.4403)
  line L2953 (27.7116, 75.4403) -> (27.7116, 74.2403)
  line L2954 (27.7116, 74.2403) -> (27.7068, 74.1423)
  line L2955 (27.7068, 74.1423) -> (27.6685, 73.95)
  line L2956 (27.6685, 73.95) -> (27.5935, 73.7689)
  line L2957 (27.5935, 73.7689) -> (27.4846, 73.6059)
  line L2958 (27.4846, 73.6059) -> (27.346, 73.4673)
  line L2959 (27.346, 73.4673) -> (27.183, 73.3584)
  line L2960 (27.183, 73.3584) -> (27.0019, 73.2833)
  line L2961 (27.0019, 73.2833) -> (26.8096, 73.2451)
  line L2962 (26.8096, 73.2451) -> (26.6136, 73.2451)
  line L2963 (26.6136, 73.2451) -> (26.4213, 73.2833)
  line L2964 (26.4213, 73.2833) -> (26.2402, 73.3584)
  line L2965 (26.2402, 73.3584) -> (26.0772, 73.4673)
  line L2966 (26.0772, 73.4673) -> (25.9386, 73.6059)
  line L2967 (25.9386, 73.6059) -> (25.8297, 73.7689)
  line L2968 (25.8297, 73.7689) -> (25.7547, 73.95)
  line L2969 (25.7547, 73.95) -> (25.7164, 74.1423)
  line L2970 (25.7164, 74.1423) -> (25.7116, 74.2403)
  line L2971 (25.7116, 74.2403) -> (25.7116, 75.4403)
  line L2972 (25.7116, 75.4403) -> (25.7164, 75.5383)
  line L2973 (25.7164, 75.5383) -> (25.7547, 75.7306)
  line L2974 (25.7547, 75.7306) -> (25.8297, 75.9117)
  line L2975 (25.8297, 75.9117) -> (25.9386, 76.0747)
  line L2976 (25.9386, 76.0747) -> (26.0772, 76.2133)
  line L2977 (26.0772, 76.2133) -> (26.2402, 76.3222)
  line L2978 (26.2402, 76.3222) -> (26.4213, 76.3972)
  line L2979 (26.4213, 76.3972) -> (26.6136, 76.4355)
  line L2980 (26.6136, 76.4355) -> (26.8096, 76.4355)
  line L2981 (26.8096, 76.4355) -> (27.0019, 76.3972)
  line L2982 (29.7319, 76.3972) -> (29.913, 76.3222)
  line L2983 (29.913, 76.3222) -> (30.076, 76.2133)
  line L2984 (30.076, 76.2133) -> (30.2146, 76.0747)
  line L2985 (30.2146, 76.0747) -> (30.3235, 75.9117)
  line L2986 (30.3235, 75.9117) -> (30.3985, 75.7306)
  line L2987 (30.3985, 75.7306) -> (30.4368, 75.5383)
  line L2988 (30.4368, 75.5383) -> (30.4416, 75.4403)
  line L2989 (30.4416, 75.4403) -> (30.4416, 74.2403)
  line L2990 (30.4416, 74.2403) -> (30.4368, 74.1423)
  line L2991 (30.4368, 74.1423) -> (30.3985, 73.95)
  line L2992 (30.3985, 73.95) -> (30.3235, 73.7689)
  line L2993 (30.3235, 73.7689) -> (30.2146, 73.6059)
  line L2994 (30.2146, 73.6059) -> (30.076, 73.4673)
  line L2995 (30.076, 73.4673) -> (29.913, 73.3584)
  line L2996 (29.913, 73.3584) -> (29.7319, 73.2833)
  line L2997 (29.7319, 73.2833) -> (29.5396, 73.2451)
  line L2998 (29.5396, 73.2451) -> (29.3436, 73.2451)
  line L2999 (29.3436, 73.2451) -> (29.1513, 73.2833)
  line L3000 (29.1513, 73.2833) -> (28.9702, 73.3584)
  line L3001 (28.9702, 73.3584) -> (28.8072, 73.4673)
  line L3002 (28.8072, 73.4673) -> (28.6686, 73.6059)
  line L3003 (28.6686, 73.6059) -> (28.5597, 73.7689)
  line L3004 (28.5597, 73.7689) -> (28.4847, 73.95)
  line L3005 (28.4847, 73.95) -> (28.4464, 74.1423)
  line L3006 (28.4464, 74.1423) -> (28.4416, 74.2403)
  line L3007 (28.4416, 74.2403) -> (28.4416, 75.4403)
  line L3008 (28.4416, 75.4403) -> (28.4464, 75.5383)
  line L3009 (28.4464, 75.5383) -> (28.4847, 75.7306)
  line L3010 (28.4847, 75.7306) -> (28.5597, 75.9117)
  line L3011 (28.5597, 75.9117) -> (28.6686, 76.0747)
  line L3012 (28.6686, 76.0747) -> (28.8072, 76.2133)
  line L3013 (28.8072, 76.2133) -> (28.9702, 76.3222)
  line L3014 (28.9702, 76.3222) -> (29.1513, 76.3972)
  line L3015 (29.1513, 76.3972) -> (29.3436, 76.4355)
  line L3016 (29.3436, 76.4355) -> (29.5396, 76.4355)
  line L3017 (29.5396, 76.4355) -> (29.7319, 76.3972)
  line L3018 (61.9269, 76.3972) -> (62.108, 76.3222)
  line L3019 (62.108, 76.3222) -> (62.271, 76.2133)
  line L3020 (62.271, 76.2133) -> (62.4096, 76.0747)
  line L3021 (62.4096, 76.0747) -> (62.5185, 75.9117)
  line L3022 (62.5185, 75.9117) -> (62.5935, 75.7306)
  line L3023 (62.5935, 75.7306) -> (62.6318, 75.5383)
  line L3024 (62.6318, 75.5383) -> (62.6366, 75.4403)
  line L3025 (62.6366, 75.4403) -> (62.6366, 74.2403)
  line L3026 (62.6366, 74.2403) -> (62.6318, 74.1423)
  line L3027 (62.6318, 74.1423) -> (62.5935, 73.95)
  line L3028 (62.5935, 73.95) -> (62.5185, 73.7689)
  line L3029 (62.5185, 73.7689) -> (62.4096, 73.6059)
  line L3030 (62.4096, 73.6059) -> (62.271, 73.4673)
  line L3031 (62.271, 73.4673) -> (62.108, 73.3584)
  line L3032 (62.108, 73.3584) -> (61.9269, 73.2833)
  line L3033 (61.9269, 73.2833) -> (61.7346, 73.2451)
  line L3034 (61.7346, 73.2451) -> (61.5386, 73.2451)
  line L3035 (61.5386, 73.2451) -> (61.3463, 73.2833)
  line L3036 (61.3463, 73.2833) -> (61.1652, 73.3584)
  line L3037 (61.1652, 73.3584) -> (61.0022, 73.4673)
  line L3038 (61.0022, 73.4673) -> (60.8636, 73.6059)
  line L3039 (60.8636, 73.6059) -> (60.7547, 73.7689)
  line L3040 (60.7547, 73.7689) -> (60.6797, 73.95)
  line L3041 (60.6797, 73.95) -> (60.6414, 74.1423)
  line L3042 (60.6414, 74.1423) -> (60.6366, 74.2403)
  line L3043 (60.6366, 74.2403) -> (60.6366, 75.4403)
  line L3044 (60.6366, 75.4403) -> (60.6414, 75.5383)
  line L3045 (60.6414, 75.5383) -> (60.6797, 75.7306)
  line L3046 (60.6797, 75.7306) -> (60.7547, 75.9117)
  line L3047 (60.7547, 75.9117) -> (60.8636, 76.0747)
  line L3048 (60.8636, 76.0747) -> (61.0022, 76.2133)
  line L3049 (61.0022, 76.2133) -> (61.1652, 76.3222)
  line L3050 (61.1652, 76.3222) -> (61.3463, 76.3972)
  line L3051 (61.3463, 76.3972) -> (61.5386, 76.4355)
  line L3052 (61.5386, 76.4355) -> (61.7346, 76.4355)
  line L3053 (61.7346, 76.4355) -> (61.9269, 76.3972)
  line L3054 (64.6569, 76.3972) -> (64.838, 76.3222)
  line L3055 (64.838, 76.3222) -> (65.001, 76.2133)
  line L3056 (65.001, 76.2133) -> (65.1396, 76.0747)
  line L3057 (65.1396, 76.0747) -> (65.2485, 75.9117)
  line L3058 (65.2485, 75.9117) -> (65.3235, 75.7306)
  line L3059 (65.3235, 75.7306) -> (65.3618, 75.5383)
  line L3060 (65.3618, 75.5383) -> (65.3666, 75.4403)
  line L3061 (65.3666, 75.4403) -> (65.3666, 74.2403)
  line L3062 (65.3666, 74.2403) -> (65.3618, 74.1423)
  line L3063 (65.3618, 74.1423) -> (65.3235, 73.95)
  line L3064 (65.3235, 73.95) -> (65.2485, 73.7689)
  line L3065 (65.2485, 73.7689) -> (65.1396, 73.6059)
  line L3066 (65.1396, 73.6059) -> (65.001, 73.4673)
  line L3067 (65.001, 73.4673) -> (64.838, 73.3584)
  line L3068 (64.838, 73.3584) -> (64.6569, 73.2833)
  line L3069 (64.6569, 73.2833) -> (64.4646, 73.2451)
  line L3070 (64.4646, 73.2451) -> (64.2686, 73.2451)
  line L3071 (64.2686, 73.2451) -> (64.0763, 73.2833)
  line L3072 (64.0763, 73.2833) -> (63.8952, 73.3584)
  line L3073 (63.8952, 73.3584) -> (63.7322, 73.4673)
  line L3074 (63.7322, 73.4673) -> (63.5936, 73.6059)
  line L3075 (63.5936, 73.6059) -> (63.4847, 73.7689)
  line L3076 (63.4847, 73.7689) -> (63.4097, 73.95)
  line L3077 (63.4097, 73.95) -> (63.3714, 74.1423)
  line L3078 (63.3714, 74.1423) -> (63.3666, 74.2403)
  line L3079 (63.3666, 74.2403) -> (63.3666, 75.4403)
  line L3080 (63.3666, 75.4403) -> (63.3714, 75.5383)
  line L3081 (63.3714, 75.5383) -> (63.4097, 75.7306)
  line L3082 (63.4097, 75.7306) -> (63.4847, 75.9117)
  line L3083 (63.4847, 75.9117) -> (63.5936, 76.0747)
  line L3084 (63.5936, 76.0747) -> (63.7322, 76.2133)
  line L3085 (63.7322, 76.2133) -> (63.8952, 76.3222)
  line L3086 (63.8952, 76.3222) -> (64.0763, 76.3972)
  line L3087 (64.0763, 76.3972) -> (64.2686, 76.4355)
  line L3088 (64.2686, 76.4355) -> (64.4646, 76.4355)
  line L3089 (64.4646, 76.4355) -> (64.6569, 76.3972)
  line L3090 (96.8519, 76.3972) -> (97.033, 76.3222)
  line L3091 (97.033, 76.3222) -> (97.196, 76.2133)
  line L3092 (97.196, 76.2133) -> (97.3346, 76.0747)
  line L3093 (97.3346, 76.0747) -> (97.4435, 75.9117)
  line L3094 (97.4435, 75.9117) -> (97.5185, 75.7306)
  line L3095 (97.5185, 75.7306) -> (97.5568, 75.5383)
  line L3096 (97.5568, 75.5383) -> (97.5616, 75.4403)
  line L3097 (97.5616, 75.4403) -> (97.5616, 74.2403)
  line L3098 (97.5616, 74.2403) -> (97.5568, 74.1423)
  line L3099 (97.5568, 74.1423) -> (97.5185, 73.95)
  line L3100 (97.5185, 73.95) -> (97.4435, 73.7689)
  line L3101 (97.4435, 73.7689) -> (97.3346, 73.6059)
  line L3102 (97.3346, 73.6059) -> (97.196, 73.4673)
  line L3103 (97.196, 73.4673) -> (97.033, 73.3584)
  line L3104 (97.033, 73.3584) -> (96.8519, 73.2833)